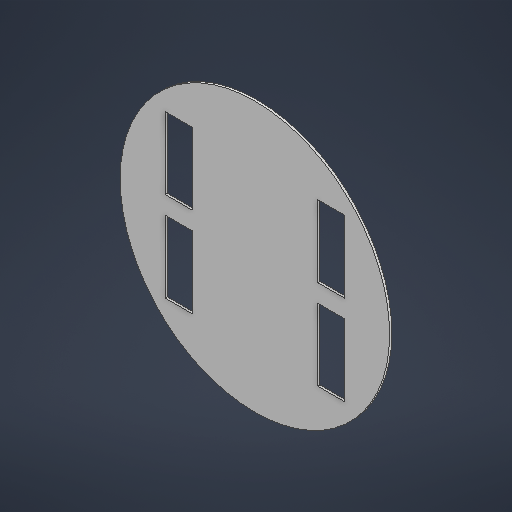
# Autodesk Inventor part: plate2.0
Saved by Autodesk Inventor 2025.2 (Build 292293000, 293)
## iProperties
Created: 2024-12-25
Part Number: plate2.0
Material: Generic
Document SubType Name: Modeling
Designer: user
Density: 1 g/cm^3
Appearance: Default
Author: user
Autodesk Inventor part; units mm, degrees
ref_plane "YZ Plane" through (0, 0, 0) normal (1, 0, 0) x (0, 1, 0)
ref_plane "XZ Plane" through (0, 0, 0) normal (0, 1, 0) x (-1, 0, 0)
ref_plane "XY Plane" through (0, 0, 0) normal (0, 0, 1) x (1, 0, 0)
sketch "Sketch1" plane through (0, 0, 0) normal (0, 0, 1) x (1, 0, 0)
  circle A0 centre (0, 0) radius 300
  dimension "d0" = 600
  constraints: 1 centre point, 1 coincident
  measures "d0" diameter of A0
extrude "Extrusion1" add sketch "Sketch1" along normal blind 5
sketch "Sketch2" plane through (0, 0, 0) normal (0, 0, -1) x (-1, 0, 0)
  line L0 (200, -179.8745) -> (140, -179.8745)
  line L1 (140, -179.8745) -> (140, -19.8745)
  line L2 (140, -19.8745) -> (200, -19.8745)
  line L3 (200, -19.8745) -> (200, -179.8745)
  circle A0 centre (0, 0) radius 300 construction
  line L4 (300, 0) -> (300, -300) construction
  line L5 (0, -300) -> (300, -300) construction
  line L6 (0, 0) -> (0, -223.3947) construction
  line L7 (0, 0) -> (300, 0) construction
  line L8 (-200, -179.8745) -> (-140, -179.8745)
  line L9 (-140, -179.8745) -> (-140, -19.8745)
  line L10 (-140, -19.8745) -> (-200, -19.8745)
  line L11 (-200, -19.8745) -> (-200, -179.8745)
  line L12 (200, 179.8745) -> (140, 179.8745)
  line L13 (140, 179.8745) -> (140, 19.8745)
  line L14 (140, 19.8745) -> (200, 19.8745)
  line L15 (200, 19.8745) -> (200, 179.8745)
  line L16 (-140, 179.8745) -> (-140, 19.8745)
  line L17 (-200, 179.8745) -> (-140, 179.8745)
  line L18 (-200, 19.8745) -> (-200, 179.8745)
  line L19 (-140, 19.8745) -> (-200, 19.8745)
  dimension "d3" = 60
  dimension "d4" = 160
  dimension "d5" = 100
  constraints: 40 end point, 12 symmetric about line, 3 horizontal, 2 parallel, 2 point on circle, 2 vertical, 1 perpendicular, 1 tangent
  measures "d3" distance of L1.end L2.end
  measures "d4" distance of L0.end L1.end
  measures "d5" distance between parallel lines of L4 L3
extrude "Extrusion2" cut sketch "Sketch2" against normal through all
body "Solid1"
